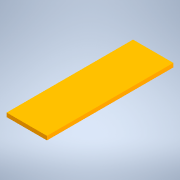
# Autodesk Inventor part: fata_sertar_inferior_trepte
Saved by Autodesk Inventor 2022.6 (Build 266554000, 554)
## iProperties
Created: 2026-10-31
Part Number: fata_sertar_inferior_trepte
Material: Generic
Document SubType Name: Modeling
Designer: Dragos Macovei
Density: 1 g/cm^3
Appearance: Default
Author: Dragos Macovei
Autodesk Inventor part; units mm, degrees
ref_plane "YZ Plane" through (0, 0, 0) normal (1, 0, 0) x (0, 1, 0)
ref_plane "XZ Plane" through (0, 0, 0) normal (0, 1, 0) x (-1, 0, 0)
ref_plane "XY Plane" through (0, 0, 0) normal (0, 0, 1) x (1, 0, 0)
sketch "Sketch1" plane through (0, 0, 0) normal (0, 1, 0) x (-1, 0, 0)
  line L0 (-101.7329, -1959.5668) -> (-266.7329, -1959.5668)
  line L1 (-266.7329, -1959.5668) -> (-266.7329, -2476.5668)
  line L2 (-266.7329, -2476.5668) -> (-101.7329, -2476.5668)
  line L3 (-101.7329, -2476.5668) -> (-101.7329, -1959.5668)
  point P0 (0, 0)
  dimension "d0" = 165
  dimension "d3" = 517
  constraints: 8 end point, 2 parallel, 1 horizontal, 1 perpendicular
  measures "d0" distance of L2.end L1.end
  measures "d3" distance of L0.end L1.end
extrude "Extrusion1" add sketch "Sketch1" along normal blind 16
body "Solid1"
